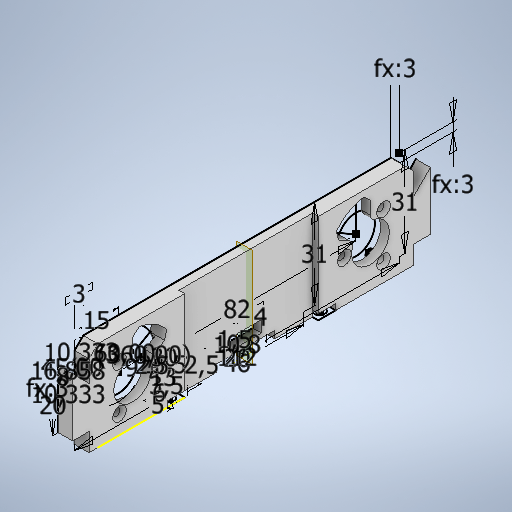
# Autodesk Inventor part: fast_motors
Saved by Autodesk Inventor 2025 (Build 290162000, 162)
## iProperties
Created: 2026-11-08
Part Number: fast_motors
Material: Типовые
Document SubType Name: Modeling
Designer: garin
Density: 1 g/cm^3
Appearance: По умолчанию
Author: garin
Autodesk Inventor part; units mm, degrees
ref_plane "YZ Plane" through (0, 0, 0) normal (1, 0, 0) x (0, 1, 0)
ref_plane "XZ Plane" through (0, 0, 0) normal (0, 1, 0) x (-1, 0, 0)
ref_plane "XY Plane" through (0, 0, 0) normal (0, 0, 1) x (1, 0, 0)
sketch "Эскиз1" plane through (0, 0, 0) normal (1, 0, 0) x (0, 1, 0)
  line L0 (0, 41) -> (0, -41) construction
  line L1 (0, 41) -> (0, 32) construction
  circle A0 centre (0, 32) radius 1.25
  circle A1 centre (7.7942, 45.5) radius 1.25
  circle A2 centre (-7.7942, 45.5) radius 1.25
  circle A3 centre (0, 41) radius 12.75
  circle A4 centre (0, 41) radius 15
  line L2 (0, 41) -> (15, 41)
  line L3 (0, 41) -> (7.5, 28.0096)
  line L4 (0, 41) -> (15, 41) construction
  line L5 (0, 41) -> (16.858, 41) construction
  line L6 (16.858, 41) -> (16.858, 56) construction
  line L7 (16.858, 56) -> (0, 56) construction
  line L8 (0, 56) -> (0, 41) construction
  line L9 (13.858, 56) -> (-14.142, 56)
  line L10 (-14.142, 56) -> (-14.142, -56)
  line L11 (-14.142, -56) -> (13.858, -56)
  line L12 (16.858, -53) -> (16.858, 53)
  line L13 (16.858, 56) -> (6.5247, 56) construction
  line L14 (6.5247, 56) -> (-3.8087, 56) construction
  line L15 (-12.75, 41) -> (-12.75, 48.9017)
  line L16 (-12.75, 41) -> (-12.75, 33.0983)
  line L17 (6.5247, 56) -> (12.1815, 61.6569)
  line L18 (6.5247, 56) -> (14.5247, 56) construction
  line L19 (12.1815, 61.6569) -> (-7.8185, 61.6569)
  line L20 (-7.8185, 61.6569) -> (-7.8185, 56)
  line L21 (16.858, 0) -> (-14.142, 0) construction
  circle A5 centre (0, -32) radius 1.25
  circle A6 centre (7.7942, -45.5) radius 1.25
  circle A7 centre (-7.7942, -45.5) radius 1.25
  circle A8 centre (0, -41) radius 12.75
  circle A9 centre (0, -41) radius 15
  line L22 (0, -41) -> (15, -41)
  line L23 (0, -41) -> (7.5, -28.0096)
  line L24 (-12.75, -41) -> (-12.75, -48.9017)
  line L25 (-12.75, -41) -> (-12.75, -33.0983)
  line L26 (6.5247, -56) -> (12.1815, -61.6569)
  line L27 (12.1815, -61.6569) -> (-7.8185, -61.6569)
  line L28 (-7.8185, -61.6569) -> (-7.8185, -56)
  circle A10 centre (0, 41) radius 6.5
  circle A11 centre (0, -41) radius 6.5
  line L29 (16.858, 53) -> (13.858, 56)
  line L30 (16.858, -53) -> (13.858, -56)
  line L31 (-11.642, -10) -> (-14.142, -10)
  line L32 (-14.142, -10) -> (-14.142, 10)
  line L33 (-14.142, 10) -> (-11.642, 10)
  line L34 (-11.642, 10) -> (-11.642, -10)
  line L35 (16.858, 23) -> (-14.142, 23)
  line L36 (-14.142, 23) -> (-14.142, -23)
  line L37 (-14.142, -23) -> (16.858, -23)
  line L38 (16.858, -23) -> (16.858, 23)
  line L39 (-11.642, 0) -> (-10.142, 0) construction
  line L40 (-6.142, 5.4) -> (-10.142, 5.4)
  line L41 (-10.142, 5.4) -> (-10.142, -5.4)
  line L42 (-10.142, -5.4) -> (-6.142, -5.4)
  line L43 (-6.142, -5.4) -> (-6.142, 5.4)
  point P0 (0, 0)
  point P1 (0, 0)
  point P2 (16.858, -56)
  point P3 (12.75, -41)
  point P4 (6.5, -41)
  point P5 (3.25, -35.3708)
  point P6 (6.375, -29.9582)
  point P7 (12.75, 41)
  point P8 (6.375, 29.9582)
  point P9 (3.25, 35.3708)
  point P10 (6.5, 41)
  dimension "d7" = 25.5
  dimension "d0" = 82
  dimension "d1" = 9
  dimension "d2" = 2.5
  dimension "d5" = 360
  dimension "d8" = 30
  dimension "d9" = 60
  dimension "d10" = 16.858
  dimension "d11" = 15
  dimension "d12" = 31
  dimension "d13" = 112
  dimension "d14" = 10.3333
  dimension "d15" = 10.3333
  dimension "d16" = 8
  dimension "d17" = 45
  dimension "d18" = 20
  dimension "d19" = 13
  dimension "d20" = 3
  dimension "d21" = 3
  dimension "d22" = 3
  dimension "d23" = 3
  dimension "d34" = 2.5
  dimension "d35" = 20
  dimension "d40" = 31
  dimension "d41" = 46
  dimension "d42" = 1.5
  dimension "d43" = 4
  dimension "d44" = 10.8
  constraints: 88 end point, 15 symmetric about line, 11 point on line, 10 centre point, 10 horizontal, 10 parallel, 8 point on circle, 7 midpoint, 6 coincident, 6 perpendicular, 3 vertical, 2 equal length, 18 other
  measures "d0" distance of L0.start L0.end
  measures "d1" distance of L0.start L1.end
  measures "d2" diameter of A0
  measures "d8" diameter of A4
  measures "d9" angle of L3 L4
  measures "d10" distance of L7.end L6.end
  measures "d11" distance of L6.end L5.end
  measures "d12" distance of point (16.858, -56) L10.end
  measures "d13" distance of L10.end L9.end
  measures "d14" distance of L6.end L13.end
  measures "d15" distance of L13.end L14.end
  measures "d16" distance of L13.end L17.end
  measures "d17" angle of L18 L17
  measures "d18" distance of L17.end L19.end
  measures "d19" diameter of A10
  measures "d20" distance of L12.end L6.end
  measures "d21" distance of L9.start L6.end
  measures "d22" distance of L12.start point (16.858, -56)
  measures "d23" distance of L11.end point (16.858, -56)
  measures "d34" distance of L32.end L33.end
  measures "d35" distance of L31.end L32.end
  measures "d40" distance of L37.end L36.end
  measures "d41" distance of L36.end L35.end
  measures "d42" distance of L39.end L39.start
  measures "d43" distance of L42.end L41.end
  measures "d44" distance of L41.end L40.end
extrude "Выдавливание1" add sketch "Эскиз1" along normal blind 5 contours L2 A10 L3 A3 | A3 L15 A4 L2 | L16 A4 L10 L15 | A3 L3 A4 L16 | A4 L9 L29 L12 L35 L10 | A4 L10 L9 | L9 L20 L19 L17 | L35 L12 L37 L10 L31 L34 L33 | L12 L30 L11 A9 L10 L37 | A9 L25 L24 L10 | A9 L11 L10 | A9 L23 A8 L25 | L26 L27 L28 L11 | L24 A8 L22 A9 | A8 L23 A11 L22 picked at (3.625, 32.443) picked at (3.625, -32.443)
extrude "Выдавливание2" cut sketch "Эскиз1" along normal blind 2 contours A0 | A1 | A2 | L2 A10 L3 A3 | A3 L3 A10 L2 | A10 L3 L2 | L2 L3 A10 | A8 L23 A11 L22 | A8 L22 A11 L23 | A11 L22 L23 | L23 L22 A11 | A5 | A6 | A7
chamfer "Фаска1" distance 2.25 angle 45 4 edges at (2.5, 7.5, -28.0096) (2.5, 15, -41) (2.5, 15, 41) (2.5, 7.5, 28.0096)
sketch "Эскиз2" plane through (0, -7.8185, -61.6569) normal (0, -1, 0) x (1, 0, 0)
  line L0 (0, 0) -> (5, 0) construction
  line L1 (0, 0) -> (5, 0) construction
  line L2 (5, 0) -> (5, 5.6569) construction
  line L3 (5, 5.6569) -> (0, 5.6569) construction
  line L4 (0, 5.6569) -> (0, 0) construction
  line L5 (0, 2.8284) -> (5, 2.8284) construction
  line L6 (2.5, 0) -> (2.5, 5.6569) construction
  circle A0 centre (2.5, 2.8284) radius 1.8
  line L7 (0, 61.6569) -> (5, 61.6569) construction
  line L8 (5, 117.6569) -> (5, 5.6569) construction
  circle A1 centre (2.5, 120.4853) radius 1.8
  dimension "d31" = 3.6
  constraints: 14 end point, 6 midpoint, 2 centre point, 2 parallel, 1 horizontal, 1 perpendicular, 1 symmetric about line, 1 other
  measures "d31" diameter of A0
extrude "Выдавливание3" cut sketch "Эскиз2" against normal blind 6
fillet "Сопряжение1" radius 2 4 edges at (3.5, 6.5, -41) (3.5, 3.25, -35.3708) (3.5, 6.5, 41) (3.5, 3.25, 35.3708)
ref_plane "РабПлоскость1" through (0, -7.8185, 0) normal (0, 0, -1) x (-1, 0, 0)
extrude "Выдавливание4" cut sketch "Эскиз1" against normal blind 2 from surface at 5 contours L35 L12 L37 L10 L31 L34 L33
sketch "Эскиз4" plane through (0, -14.142, 10) normal (0, -1, 0) x (1, 0, 0)
  line L0 (5, 13) -> (5, 43) projected
  line L1 (5, 13) -> (0, 13)
  line L2 (0, 13) -> (0, 19)
  line L3 (0, 19) -> (5, 19)
  line L4 (5, 19) -> (5, 13)
  line L5 (3, -4.6) -> (3, -15.4) construction
  line L6 (3, -10) -> (0, -10) construction
  line L7 (0, -4.6) -> (0, -15.4) construction
  line L8 (5, 16) -> (0, 16) construction
  line L9 (2.5, 19) -> (2.5, 13) construction
  circle A0 centre (2.5, 16) radius 1.75
  line L10 (5, -33) -> (0, -33)
  line L11 (0, -33) -> (0, -39)
  line L12 (0, -39) -> (5, -39)
  line L13 (5, -39) -> (5, -33)
  line L14 (5, -36) -> (0, -36) construction
  line L15 (2.5, -39) -> (2.5, -33) construction
  circle A1 centre (2.5, -36) radius 1.75
  dimension "d47" = 5
  dimension "d48" = 6
  dimension "d49" = 3.5
  constraints: 26 end point, 9 symmetric about line, 6 midpoint, 2 centre point, 2 parallel, 2 perpendicular, 1 horizontal, 1 other
  measures "d47" distance of L2.end L3.end
  measures "d48" distance of L1.end L2.end
  measures "d49" diameter of A0
extrude "Выдавливание5" cut sketch "Эскиз4" against normal blind 6 contours A0 | A1
extrude "Выдавливание6" cut sketch "Эскиз4" against normal blind 2
chamfer "Фаска2" distance 1.1 angle 45 6 edges at (5, 6.5442, 45.5) (5, -1.25, 32) (5, -9.0442, 45.5) (5, 6.5442, -45.5) (5, -1.25, -32) (5, -9.0442, -45.5)
equation "\"d21\" = d20"
equation "\"d22\" = d20"
equation "\"d23\" = d22"
